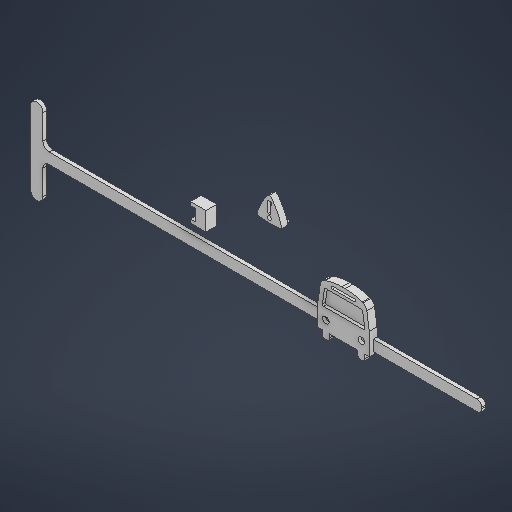
# Autodesk Inventor part: Bus
Saved by Autodesk Inventor 2027 (Build 310192060, 192F)
## iProperties
Created: 2025-09-19
Part Number: Bus
Material: Genérico
Document SubType Name: Modeling
Designer: Pablo
Density: 1 g/cm^3
Appearance: Valor por defecto
Author: Pablo
Autodesk Inventor part; units mm, degrees
(part 1 of 2)
ref_plane "YZ Plane" through (0, 0, 0) normal (1, 0, 0) x (0, 1, 0)
ref_plane "XZ Plane" through (0, 0, 0) normal (0, 1, 0) x (-1, 0, 0)
ref_plane "XY Plane" through (0, 0, 0) normal (0, 0, 1) x (1, 0, 0)
sketch "Boceto1" plane through (0, 0, 0) normal (0, 0, 1) x (1, 0, 0)
  spline S0 degree 3 poles (40.8616, 31.8557) (40.8616, 34.2295) (40.8616, 36.6032) (40.8611, 38.977) knots 0 0 0 0 1 1 1 1
  line L0 (40.8616, 31.8557) -> (40.8616, 34.2295) construction
  line L1 (40.8616, 34.2295) -> (40.8616, 36.6032) construction
  line L2 (40.8616, 36.6032) -> (40.8611, 38.977) construction
  spline S1 degree 3 poles (40.8611, 38.977) (40.8611, 38.9994) (40.8575, 39.0217) (40.856, 39.0441) knots 1 1 1 1 2 2 2 2
  line L3 (40.8611, 38.977) -> (40.8611, 38.9994) construction
  line L4 (40.8611, 38.9994) -> (40.8575, 39.0217) construction
  line L5 (40.8575, 39.0217) -> (40.856, 39.0441) construction
  spline S2 degree 3 poles (40.856, 39.0441) (40.856, 39.3464) (40.856, 39.6488) (40.856, 39.9511) knots 2 2 2 2 3 3 3 3
  line L6 (40.856, 39.0441) -> (40.856, 39.3464) construction
  line L7 (40.856, 39.3464) -> (40.856, 39.6488) construction
  line L8 (40.856, 39.6488) -> (40.856, 39.9511) construction
  spline S3 degree 3 poles (40.856, 39.9511) (40.856, 40.0019) (40.852, 40.053) (40.8445, 40.1033) knots 3 3 3 3 4 4 4 4
  line L9 (40.856, 39.9511) -> (40.856, 40.0019) construction
  line L10 (40.856, 40.0019) -> (40.852, 40.053) construction
  line L11 (40.852, 40.053) -> (40.8445, 40.1033) construction
  spline S4 degree 3 poles (40.8445, 40.1033) (40.7707, 40.601) (40.6955, 41.0985) (40.6214, 41.5961) knots 4 4 4 4 5 5 5 5
  line L12 (40.8445, 40.1033) -> (40.7707, 40.601) construction
  line L13 (40.7707, 40.601) -> (40.6955, 41.0985) construction
  line L14 (40.6955, 41.0985) -> (40.6214, 41.5961) construction
  spline S5 degree 3 poles (40.6214, 41.5961) (40.5322, 42.1946) (40.4442, 42.7933) (40.3549, 43.3918) knots 5 5 5 5 6 6 6 6
  line L15 (40.6214, 41.5961) -> (40.5322, 42.1946) construction
  line L16 (40.5322, 42.1946) -> (40.4442, 42.7933) construction
  line L17 (40.4442, 42.7933) -> (40.3549, 43.3918) construction
  spline S6 degree 3 poles (40.3549, 43.3918) (40.265, 43.9937) (40.1747, 44.5954) (40.0834, 45.1971) knots 6 6 6 6 7 7 7 7
  line L18 (40.3549, 43.3918) -> (40.265, 43.9937) construction
  line L19 (40.265, 43.9937) -> (40.1747, 44.5954) construction
  line L20 (40.1747, 44.5954) -> (40.0834, 45.1971) construction
  spline S7 degree 3 poles (40.0834, 45.1971) (40.0103, 45.68) (39.7786, 46.0909) (39.3479, 46.409) knots 7 7 7 7 8 8 8 8
  line L21 (40.0834, 45.1971) -> (40.0103, 45.68) construction
  line L22 (40.0103, 45.68) -> (39.7786, 46.0909) construction
  line L23 (39.7786, 46.0909) -> (39.3479, 46.409) construction
  spline S8 degree 3 poles (39.3479, 46.409) (38.9282, 46.7189) (38.4358, 46.9172) (37.9249, 47.0751) knots 8 8 8 8 9 9 9 9
  line L24 (39.3479, 46.409) -> (38.9282, 46.7189) construction
  line L25 (38.9282, 46.7189) -> (38.4358, 46.9172) construction
  line L26 (38.4358, 46.9172) -> (37.9249, 47.0751) construction
  spline S9 degree 3 poles (37.9249, 47.0751) (36.5997, 47.4845) (35.2232, 47.6868) (33.8295, 47.8099) knots 9 9 9 9 10 10 10 10
  line L27 (37.9249, 47.0751) -> (36.5997, 47.4845) construction
  line L28 (36.5997, 47.4845) -> (35.2232, 47.6868) construction
  line L29 (35.2232, 47.6868) -> (33.8295, 47.8099) construction
  spline S10 degree 3 poles (33.8295, 47.8099) (33.0432, 47.8793) (32.2577, 47.8666) (31.4714, 47.7946) knots 10 10 10 10 11 11 11 11
  line L30 (33.8295, 47.8099) -> (33.0432, 47.8793) construction
  line L31 (33.0432, 47.8793) -> (32.2577, 47.8666) construction
  line L32 (32.2577, 47.8666) -> (31.4714, 47.7946) construction
  spline S11 degree 3 poles (31.4714, 47.7946) (30.5096, 47.7066) (29.5599, 47.5625) (28.6214, 47.3611) knots 11 11 11 11 12 12 12 12
  line L33 (31.4714, 47.7946) -> (30.5096, 47.7066) construction
  line L34 (30.5096, 47.7066) -> (29.5599, 47.5625) construction
  line L35 (29.5599, 47.5625) -> (28.6214, 47.3611) construction
  spline S12 degree 3 poles (28.6214, 47.3611) (27.8894, 47.204) (27.1802, 46.9945) (26.5251, 46.6616) knots 12 12 12 12 13 13 13 13
  line L36 (28.6214, 47.3611) -> (27.8894, 47.204) construction
  line L37 (27.8894, 47.204) -> (27.1802, 46.9945) construction
  line L38 (27.1802, 46.9945) -> (26.5251, 46.6616) construction
  spline S13 degree 3 poles (26.5251, 46.6616) (25.8871, 46.3373) (25.4918, 45.8668) (25.386, 45.2249) knots 13 13 13 13 14 14 14 14
  line L39 (26.5251, 46.6616) -> (25.8871, 46.3373) construction
  line L40 (25.8871, 46.3373) -> (25.4918, 45.8668) construction
  line L41 (25.4918, 45.8668) -> (25.386, 45.2249) construction
  spline S14 degree 3 poles (25.386, 45.2249) (25.3274, 44.8691) (25.2811, 44.5119) (25.2281, 44.1554) knots 14 14 14 14 15 15 15 15
  line L42 (25.386, 45.2249) -> (25.3274, 44.8691) construction
  line L43 (25.3274, 44.8691) -> (25.2811, 44.5119) construction
  line L44 (25.2811, 44.5119) -> (25.2281, 44.1554) construction
  spline S15 degree 3 poles (25.2281, 44.1554) (25.146, 43.6039) (25.0628, 43.0526) (24.9803, 42.5012) knots 15 15 15 15 16 16 16 16
  line L45 (25.2281, 44.1554) -> (25.146, 43.6039) construction
  line L46 (25.146, 43.6039) -> (25.0628, 43.0526) construction
  line L47 (25.0628, 43.0526) -> (24.9803, 42.5012) construction
  spline S16 degree 3 poles (24.9803, 42.5012) (24.8978, 41.9498) (24.8143, 41.3985) (24.7336, 40.8469) knots 16 16 16 16 17 17 17 17
  line L48 (24.9803, 42.5012) -> (24.8978, 41.9498) construction
  line L49 (24.8978, 41.9498) -> (24.8143, 41.3985) construction
  line L50 (24.8143, 41.3985) -> (24.7336, 40.8469) construction
  spline S17 degree 3 poles (24.7336, 40.8469) (24.6889, 40.541) (24.614, 40.2346) (24.6127, 39.9282) knots 17 17 17 17 18 18 18 18
  line L51 (24.7336, 40.8469) -> (24.6889, 40.541) construction
  line L52 (24.6889, 40.541) -> (24.614, 40.2346) construction
  line L53 (24.614, 40.2346) -> (24.6127, 39.9282) construction
  spline S18 degree 3 poles (24.6127, 39.9282) (24.6051, 38.1413) (24.6059, 36.3544) (24.6067, 34.5675) knots 18 18 18 18 19 19 19 19
  line L54 (24.6127, 39.9282) -> (24.6051, 38.1413) construction
  line L55 (24.6051, 38.1413) -> (24.6059, 36.3544) construction
  line L56 (24.6059, 36.3544) -> (24.6067, 34.5675) construction
  spline S19 degree 3 poles (24.6067, 34.5675) (24.6065, 34.0719) (24.6063, 33.5763) (24.6065, 33.0807) knots 19 19 19 19 20 20 20 20
  line L57 (24.6067, 34.5675) -> (24.6065, 34.0719) construction
  line L58 (24.6065, 34.0719) -> (24.6063, 33.5763) construction
  line L59 (24.6063, 33.5763) -> (24.6065, 33.0807) construction
  spline S20 degree 3 poles (24.6065, 33.0807) (24.6062, 31.8371) (24.6072, 30.5935) (24.6072, 29.3499) (24.6072, 29.3132) (24.6072, 29.2766) (24.6072, 29.2237) knots 20 20 20 20 21 21 21 22 22 22 22
  line L60 (24.6065, 33.0807) -> (24.6062, 31.8371) construction
  line L61 (24.6062, 31.8371) -> (24.6072, 30.5935) construction
  line L62 (24.6072, 30.5935) -> (24.6072, 29.3499) construction
  line L63 (24.6072, 29.3499) -> (24.6072, 29.3132) construction
  line L64 (24.6072, 29.3132) -> (24.6072, 29.2766) construction
  line L65 (24.6072, 29.2766) -> (24.6072, 29.2237) construction
  spline S21 degree 3 poles (24.6072, 29.2237) (25.0641, 29.2237) (25.5097, 29.2237) (25.9657, 29.2237) knots 22 22 22 22 23 23 23 23
  line L66 (24.6072, 29.2237) -> (25.0641, 29.2237) construction
  line L67 (25.0641, 29.2237) -> (25.5097, 29.2237) construction
  line L68 (25.5097, 29.2237) -> (25.9657, 29.2237) construction
  spline S22 degree 3 poles (25.9657, 29.2237) (25.9657, 29.1676) (25.9657, 29.1275) (25.9658, 29.0874) knots 23 23 23 23 24 24 24 24
  line L69 (25.9657, 29.2237) -> (25.9657, 29.1676) construction
  line L70 (25.9657, 29.1676) -> (25.9657, 29.1275) construction
  line L71 (25.9657, 29.1275) -> (25.9658, 29.0874) construction
  spline S23 degree 3 poles (25.9658, 29.0874) (25.9661, 28.7444) (25.9588, 28.4012) (25.9685, 28.0584) knots 24 24 24 24 25 25 25 25
  line L72 (25.9658, 29.0874) -> (25.9661, 28.7444) construction
  line L73 (25.9661, 28.7444) -> (25.9588, 28.4012) construction
  line L74 (25.9588, 28.4012) -> (25.9685, 28.0584) construction
  spline S24 degree 3 poles (25.9685, 28.0584) (25.9929, 27.1984) (26.891, 26.8938) (27.5599, 27.098) knots 25 25 25 25 26 26 26 26
  line L75 (25.9685, 28.0584) -> (25.9929, 27.1984) construction
  line L76 (25.9929, 27.1984) -> (26.891, 26.8938) construction
  line L77 (26.891, 26.8938) -> (27.5599, 27.098) construction
  spline S25 degree 3 poles (27.5599, 27.098) (27.9931, 27.2303) (28.295, 27.5697) (28.3094, 27.9733) knots 26 26 26 26 27 27 27 27
  line L78 (27.5599, 27.098) -> (27.9931, 27.2303) construction
  line L79 (27.9931, 27.2303) -> (28.295, 27.5697) construction
  line L80 (28.295, 27.5697) -> (28.3094, 27.9733) construction
  spline S26 degree 3 poles (28.3094, 27.9733) (28.3227, 28.3465) (28.3153, 28.7203) (28.3169, 29.0939) knots 27 27 27 27 28 28 28 28
  line L81 (28.3094, 27.9733) -> (28.3227, 28.3465) construction
  line L82 (28.3227, 28.3465) -> (28.3153, 28.7203) construction
  line L83 (28.3153, 28.7203) -> (28.3169, 29.0939) construction
  spline S27 degree 3 poles (28.3169, 29.0939) (28.3171, 29.1335) (28.317, 29.1732) (28.317, 29.2165) knots 28 28 28 28 29 29 29 29
  line L84 (28.3169, 29.0939) -> (28.3171, 29.1335) construction
  line L85 (28.3171, 29.1335) -> (28.317, 29.1732) construction
  line L86 (28.317, 29.1732) -> (28.317, 29.2165) construction
  spline S28 degree 3 poles (28.317, 29.2165) (31.2685, 29.2165) (34.2031, 29.2165) (37.1493, 29.2165) knots 29 29 29 29 30 30 30 30
  line L87 (28.317, 29.2165) -> (31.2685, 29.2165) construction
  line L88 (31.2685, 29.2165) -> (34.2031, 29.2165) construction
  line L89 (34.2031, 29.2165) -> (37.1493, 29.2165) construction
  spline S29 degree 3 poles (37.1493, 29.2165) (37.1493, 29.1729) (37.1493, 29.1363) (37.1493, 29.0996) knots 30 30 30 30 31 31 31 31
  line L90 (37.1493, 29.2165) -> (37.1493, 29.1729) construction
  line L91 (37.1493, 29.1729) -> (37.1493, 29.1363) construction
  line L92 (37.1493, 29.1363) -> (37.1493, 29.0996) construction
  spline S30 degree 3 poles (37.1493, 29.0996) (37.1495, 28.7465) (37.1476, 28.3933) (37.1509, 28.0401) knots 31 31 31 31 32 32 32 32
  line L93 (37.1493, 29.0996) -> (37.1495, 28.7465) construction
  line L94 (37.1495, 28.7465) -> (37.1476, 28.3933) construction
  line L95 (37.1476, 28.3933) -> (37.1509, 28.0401) construction
  spline S31 degree 3 poles (37.1509, 28.0401) (37.1525, 27.854) (37.2057, 27.6778) (37.3152, 27.5165) knots 32 32 32 32 33 33 33 33
  line L96 (37.1509, 28.0401) -> (37.1525, 27.854) construction
  line L97 (37.1525, 27.854) -> (37.2057, 27.6778) construction
  line L98 (37.2057, 27.6778) -> (37.3152, 27.5165) construction
  spline S32 degree 3 poles (37.3152, 27.5165) (37.5769, 27.131) (38.1197, 26.9538) (38.6595, 27.0769) knots 33 33 33 33 34 34 34 34
  line L99 (37.3152, 27.5165) -> (37.5769, 27.131) construction
  line L100 (37.5769, 27.131) -> (38.1197, 26.9538) construction
  line L101 (38.1197, 26.9538) -> (38.6595, 27.0769) construction
  spline S33 degree 3 poles (38.6595, 27.0769) (39.1527, 27.1894) (39.4892, 27.5688) (39.4966, 28.032) knots 34 34 34 34 35 35 35 35
  line L102 (38.6595, 27.0769) -> (39.1527, 27.1894) construction
  line L103 (39.1527, 27.1894) -> (39.4892, 27.5688) construction
  line L104 (39.4892, 27.5688) -> (39.4966, 28.032) construction
  spline S34 degree 3 poles (39.4966, 28.032) (39.5025, 28.3885) (39.498, 28.7451) (39.4982, 29.1017) knots 35 35 35 35 36 36 36 36
  line L105 (39.4966, 28.032) -> (39.5025, 28.3885) construction
  line L106 (39.5025, 28.3885) -> (39.498, 28.7451) construction
  line L107 (39.498, 28.7451) -> (39.4982, 29.1017) construction
  spline S35 degree 3 poles (39.4982, 29.1017) (39.4982, 29.1381) (39.4982, 29.1745) (39.4982, 29.2229) knots 36 36 36 36 37 37 37 37
  line L108 (39.4982, 29.1017) -> (39.4982, 29.1381) construction
  line L109 (39.4982, 29.1381) -> (39.4982, 29.1745) construction
  line L110 (39.4982, 29.1745) -> (39.4982, 29.2229) construction
  spline S36 degree 3 poles (39.4982, 29.2229) (39.9535, 29.2229) (40.3962, 29.2229) (40.8565, 29.2229) knots 37 37 37 37 38 38 38 38
  line L111 (39.4982, 29.2229) -> (39.9535, 29.2229) construction
  line L112 (39.9535, 29.2229) -> (40.3962, 29.2229) construction
  line L113 (40.3962, 29.2229) -> (40.8565, 29.2229) construction
  spline S37 degree 3 poles (40.8565, 29.2229) (40.8565, 29.275) (40.8565, 29.3086) (40.8565, 29.3422) (40.8565, 29.767) (40.8564, 30.1918) (40.8564, 30.6166) knots 38 38 38 38 39 39 39 40 40 40 40
  line L114 (40.8565, 29.2229) -> (40.8565, 29.275) construction
  line L115 (40.8565, 29.275) -> (40.8565, 29.3086) construction
  line L116 (40.8565, 29.3086) -> (40.8565, 29.3422) construction
  line L117 (40.8565, 29.3422) -> (40.8565, 29.767) construction
  line L118 (40.8565, 29.767) -> (40.8564, 30.1918) construction
  line L119 (40.8564, 30.1918) -> (40.8564, 30.6166) construction
  line L120 (40.8564, 30.6166) -> (40.8565, 30.6166)
  spline S38 degree 3 poles (40.8565, 30.6166) (40.8565, 30.6686) (40.8565, 30.7022) (40.8565, 30.7359) (40.8565, 31.0694) (40.8564, 31.4029) (40.8564, 31.7364) knots 41 41 41 41 42 42 42 43 43 43 43
  line L121 (40.8565, 30.6166) -> (40.8565, 30.6686) construction
  line L122 (40.8565, 30.6686) -> (40.8565, 30.7022) construction
  line L123 (40.8565, 30.7022) -> (40.8565, 30.7359) construction
  line L124 (40.8565, 30.7359) -> (40.8565, 31.0694) construction
  line L125 (40.8565, 31.0694) -> (40.8564, 31.4029) construction
  line L126 (40.8564, 31.4029) -> (40.8564, 31.7364) construction
  spline S39 degree 3 poles (40.8564, 31.7364) (40.8581, 31.7364) (40.8598, 31.7364) (40.8616, 31.7364) knots 43 43 43 43 44 44 44 44
  line L127 (40.8564, 31.7364) -> (40.8581, 31.7364) construction
  line L128 (40.8581, 31.7364) -> (40.8598, 31.7364) construction
  line L129 (40.8598, 31.7364) -> (40.8616, 31.7364) construction
  spline S40 degree 3 poles (40.8616, 31.7364) (40.8616, 31.7885) (40.8616, 31.8221) (40.8616, 31.8557) knots 44 44 44 44 45 45 45 45
  line L130 (40.8616, 31.7364) -> (40.8616, 31.7885) construction
  line L131 (40.8616, 31.7885) -> (40.8616, 31.8221) construction
  line L132 (40.8616, 31.8221) -> (40.8616, 31.8557) construction
  spline S41 degree 3 poles (34.2345, 42.6962) (35.0073, 42.6962) (35.7802, 42.6959) (36.553, 42.6956) (36.5571, 42.6769) (36.5618, 42.6586) (36.5635, 42.6386) (36.586, 42.3716) (36.3803, 42.1817) (36.0592, 42.1812) (34.9481, 42.1798) (33.837, 42.1807) (32.7258, 42.1807) (31.6225, 42.1806) (30.5192, 42.18) (29.4159, 42.181) (29.128, 42.1813) (28.9588, 42.3013) (28.9123, 42.5307) (28.9007, 42.5881) (28.903, 42.6429) (28.9139, 42.6946) (30.6875, 42.6957) (32.461, 42.696) (34.2345, 42.6962) knots 0 0 0 0 1 1 1 2 2 2 3 3 3 4 4 4 5 5 5 6 6 6 7 7 7 8 8 8 8
  line L133 (34.2345, 42.6962) -> (35.0073, 42.6962) construction
  line L134 (35.0073, 42.6962) -> (35.7802, 42.6959) construction
  line L135 (35.7802, 42.6959) -> (36.553, 42.6956) construction
  line L136 (36.553, 42.6956) -> (36.5571, 42.6769) construction
  line L137 (36.5571, 42.6769) -> (36.5618, 42.6586) construction
  line L138 (36.5618, 42.6586) -> (36.5635, 42.6386) construction
  line L139 (36.5635, 42.6386) -> (36.586, 42.3716) construction
  line L140 (36.586, 42.3716) -> (36.3803, 42.1817) construction
  line L141 (36.3803, 42.1817) -> (36.0592, 42.1812) construction
  line L142 (36.0592, 42.1812) -> (34.9481, 42.1798) construction
  line L143 (34.9481, 42.1798) -> (33.837, 42.1807) construction
  line L144 (33.837, 42.1807) -> (32.7258, 42.1807) construction
  line L145 (32.7258, 42.1807) -> (31.6225, 42.1806) construction
  line L146 (31.6225, 42.1806) -> (30.5192, 42.18) construction
  line L147 (30.5192, 42.18) -> (29.4159, 42.181) construction
  line L148 (29.4159, 42.181) -> (29.128, 42.1813) construction
  line L149 (29.128, 42.1813) -> (28.9588, 42.3013) construction
  line L150 (28.9588, 42.3013) -> (28.9123, 42.5307) construction
  line L151 (28.9123, 42.5307) -> (28.9007, 42.5881) construction
  line L152 (28.9007, 42.5881) -> (28.903, 42.6429) construction
  line L153 (28.903, 42.6429) -> (28.9139, 42.6946) construction
  line L154 (28.9139, 42.6946) -> (30.6875, 42.6957) construction
  line L155 (30.6875, 42.6957) -> (32.461, 42.696) construction
  line L156 (32.461, 42.696) -> (34.2345, 42.6962) construction
  spline S42 degree 3 poles (26.564, 39.4612) (26.5391, 39.4643) (26.5166, 39.4697) (26.4932, 39.4744) (26.556, 39.8745) (26.6178, 40.2748) (26.6981, 40.6722) (26.7877, 41.1148) (27.0588, 41.2999) (27.5762, 41.3006) (29.7957, 41.3033) (32.0151, 41.3022) (34.2345, 41.3025) (35.4124, 41.3026) (36.5905, 41.303) (37.7684, 41.3016) (37.8849, 41.3015) (38.0023, 41.2957) (38.1176, 41.2817) (38.4206, 41.2449) (38.632, 41.0974) (38.7143, 40.8428) (38.7815, 40.6351) (38.8204, 40.4195) (38.8562, 40.2054) (38.8971, 39.9608) (38.9349, 39.7159) (38.9744, 39.4711) (38.9349, 39.4639) (38.894, 39.4585) (38.8504, 39.4567) (38.7921, 39.4542) (38.7334, 39.4555) (38.6749, 39.4555) (36.6935, 39.4554) (34.712, 39.4554) (32.7304, 39.4554) (30.745, 39.4554) (28.7597, 39.4554) (26.7743, 39.4556) (26.7041, 39.4556) (26.633, 39.4526) (26.564, 39.4612) knots 0 0 0 0 1 1 1 2 2 2 3 3 3 4 4 4 5 5 5 6 6 6 7 7 7 8 8 8 9 9 9 10 10 10 11 11 11 12 12 12 13 13 13 14 14 14 14
  line L157 (26.564, 39.4612) -> (26.5391, 39.4643) construction
  line L158 (26.5391, 39.4643) -> (26.5166, 39.4697) construction
  line L159 (26.5166, 39.4697) -> (26.4932, 39.4744) construction
  line L160 (26.4932, 39.4744) -> (26.556, 39.8745) construction
  line L161 (26.556, 39.8745) -> (26.6178, 40.2748) construction
  line L162 (26.6178, 40.2748) -> (26.6981, 40.6722) construction
  line L163 (26.6981, 40.6722) -> (26.7877, 41.1148) construction
  line L164 (26.7877, 41.1148) -> (27.0588, 41.2999) construction
  line L165 (27.0588, 41.2999) -> (27.5762, 41.3006) construction
  line L166 (27.5762, 41.3006) -> (29.7957, 41.3033) construction
  line L167 (29.7957, 41.3033) -> (32.0151, 41.3022) construction
  line L168 (32.0151, 41.3022) -> (34.2345, 41.3025) construction
  line L169 (34.2345, 41.3025) -> (35.4124, 41.3026) construction
  line L170 (35.4124, 41.3026) -> (36.5905, 41.303) construction
  line L171 (36.5905, 41.303) -> (37.7684, 41.3016) construction
  line L172 (37.7684, 41.3016) -> (37.8849, 41.3015) construction
  line L173 (37.8849, 41.3015) -> (38.0023, 41.2957) construction
  line L174 (38.0023, 41.2957) -> (38.1176, 41.2817) construction
  line L175 (38.1176, 41.2817) -> (38.4206, 41.2449) construction
  line L176 (38.4206, 41.2449) -> (38.632, 41.0974) construction
  line L177 (38.632, 41.0974) -> (38.7143, 40.8428) construction
  line L178 (38.7143, 40.8428) -> (38.7815, 40.6351) construction
  line L179 (38.7815, 40.6351) -> (38.8204, 40.4195) construction
  line L180 (38.8204, 40.4195) -> (38.8562, 40.2054) construction
  line L181 (38.8562, 40.2054) -> (38.8971, 39.9608) construction
  line L182 (38.8971, 39.9608) -> (38.9349, 39.7159) construction
  line L183 (38.9349, 39.7159) -> (38.9744, 39.4711) construction
  line L184 (38.9744, 39.4711) -> (38.9349, 39.4639) construction
  line L185 (38.9349, 39.4639) -> (38.894, 39.4585) construction
  line L186 (38.894, 39.4585) -> (38.8504, 39.4567) construction
  line L187 (38.8504, 39.4567) -> (38.7921, 39.4542) construction
  line L188 (38.7921, 39.4542) -> (38.7334, 39.4555) construction
  line L189 (38.7334, 39.4555) -> (38.6749, 39.4555) construction
  line L190 (38.6749, 39.4555) -> (36.6935, 39.4554) construction
  line L191 (36.6935, 39.4554) -> (34.712, 39.4554) construction
  line L192 (34.712, 39.4554) -> (32.7304, 39.4554) construction
  line L193 (32.7304, 39.4554) -> (30.745, 39.4554) construction
  line L194 (30.745, 39.4554) -> (28.7597, 39.4554) construction
  line L195 (28.7597, 39.4554) -> (26.7743, 39.4556) construction
  line L196 (26.7743, 39.4556) -> (26.7041, 39.4556) construction
  line L197 (26.7041, 39.4556) -> (26.633, 39.4526) construction
  line L198 (26.633, 39.4526) -> (26.564, 39.4612) construction
  spline S43 degree 3 poles (40.4002, 7.2187) (39.938, 7.2187) (39.4935, 7.2187) (39.0362, 7.2187) (39.0362, 7.1702) (39.0362, 7.1337) (39.0362, 7.0972) (39.0361, 6.7401) (39.0405, 6.3829) (39.0347, 6.0258) (39.0272, 5.5619) (38.6893, 5.1819) (38.194, 5.0692) (37.6521, 4.9459) (37.107, 5.1234) (36.8441, 5.5095) (36.7342, 5.6711) (36.6808, 5.8475) (36.6791, 6.034) (36.6759, 6.3877) (36.6778, 6.7414) (36.6775, 7.0952) (36.6775, 7.1319) (36.6775, 7.1686) (36.6775, 7.2122) (33.719, 7.2122) (30.7722, 7.2122) (27.8084, 7.2122) (27.8084, 7.1688) (27.8085, 7.1291) (27.8084, 7.0894) (27.8067, 6.7153) (27.8142, 6.3409) (27.8008, 5.9671) (27.7863, 5.5628) (27.4832, 5.2229) (27.0481, 5.0904) (26.3765, 4.8859) (25.4746, 5.1909) (25.4501, 6.0523) (25.4404, 6.3956) (25.4478, 6.7393) (25.4474, 7.0829) (25.4473, 7.1231) (25.4474, 7.1633) (25.4474, 7.2195) (24.9895, 7.2195) (24.542, 7.2195) (24.0831, 7.2195) (24.0831, 7.2724) (24.0831, 7.3091) (24.0831, 7.3458) (24.0831, 9.7132) (24.0786, 12.0805) (24.0887, 14.4478) (24.0901, 14.7547) (24.1652, 15.0615) (24.2101, 15.368) (24.2911, 15.9205) (24.375, 16.4726) (24.4579, 17.0249) (24.5407, 17.5772) (24.6242, 18.1294) (24.7066, 18.6817) (24.7599, 19.0387) (24.8064, 19.3966) (24.8652, 19.7529) (24.9714, 20.3959) (25.3684, 20.8671) (26.009, 21.1919) (26.6669, 21.5253) (27.3791, 21.7351) (28.1141, 21.8925) (29.0565, 22.0942) (30.0102, 22.2385) (30.976, 22.3267) (31.7656, 22.3988) (32.5544, 22.4116) (33.3439, 22.342) (34.7435, 22.2188) (36.1257, 22.0161) (37.4564, 21.606) (37.9694, 21.4479) (38.4638, 21.2493) (38.8853, 20.9389) (39.3179, 20.6203) (39.5504, 20.2087) (39.624, 19.7251) (39.7156, 19.1225) (39.8063, 18.5197) (39.8965, 17.9169) (39.9863, 17.3174) (40.0746, 16.7178) (40.1641, 16.1183) (40.2385, 15.6199) (40.3141, 15.1216) (40.3882, 14.6231) (40.3956, 14.5727) (40.3997, 14.5216) (40.3997, 14.4708) (40.4002, 12.0932) (40.4002, 9.7157) (40.4002, 7.3381) (40.4002, 7.3044) (40.4002, 7.2708) (40.4002, 7.2187) knots 0 0 0 0 1 1 1 2 2 2 3 3 3 4 4 4 5 5 5 6 6 6 7 7 7 8 8 8 9 9 9 10 10 10 11 11 11 12 12 12 13 13 13 14 14 14 15 15 15 16 16 16 17 17 17 18 18 18 19 19 19 20 20 20 21 21 21 22 22 22 23 23 23 24 24 24 25 25 25 26 26 26 27 27 27 28 28 28 29 29 29 30 30 30 31 31 31 32 32 32 33 33 33 34 34 34 35 35 35 35
  line L199 (40.4002, 7.2187) -> (39.938, 7.2187) construction
  line L200 (39.938, 7.2187) -> (39.4935, 7.2187) construction
  line L201 (39.4935, 7.2187) -> (39.0362, 7.2187) construction
  line L202 (39.0362, 7.2187) -> (39.0362, 7.1702) construction
  line L203 (39.0362, 7.1702) -> (39.0362, 7.1337) construction
  line L204 (39.0362, 7.1337) -> (39.0362, 7.0972) construction
  line L205 (39.0362, 7.0972) -> (39.0361, 6.7401) construction
  line L206 (39.0361, 6.7401) -> (39.0405, 6.3829) construction
  line L207 (39.0405, 6.3829) -> (39.0347, 6.0258) construction
  line L208 (39.0347, 6.0258) -> (39.0272, 5.5619) construction
  line L209 (39.0272, 5.5619) -> (38.6893, 5.1819) construction
  line L210 (38.6893, 5.1819) -> (38.194, 5.0692) construction
  line L211 (38.194, 5.0692) -> (37.6521, 4.9459) construction
  line L212 (37.6521, 4.9459) -> (37.107, 5.1234) construction
  line L213 (37.107, 5.1234) -> (36.8441, 5.5095) construction
  line L214 (36.8441, 5.5095) -> (36.7342, 5.6711) construction
  line L215 (36.7342, 5.6711) -> (36.6808, 5.8475) construction
  line L216 (36.6808, 5.8475) -> (36.6791, 6.034) construction
  line L217 (36.6791, 6.034) -> (36.6759, 6.3877) construction
  line L218 (36.6759, 6.3877) -> (36.6778, 6.7414) construction
  line L219 (36.6778, 6.7414) -> (36.6775, 7.0952) construction
  line L220 (36.6775, 7.0952) -> (36.6775, 7.1319) construction
  line L221 (36.6775, 7.1319) -> (36.6775, 7.1686) construction
  line L222 (36.6775, 7.1686) -> (36.6775, 7.2122) construction
  line L223 (36.6775, 7.2122) -> (33.719, 7.2122) construction
  line L224 (33.719, 7.2122) -> (30.7722, 7.2122) construction
  line L225 (30.7722, 7.2122) -> (27.8084, 7.2122) construction
  line L226 (27.8084, 7.2122) -> (27.8084, 7.1688) construction
  line L227 (27.8084, 7.1688) -> (27.8085, 7.1291) construction
  line L228 (27.8085, 7.1291) -> (27.8084, 7.0894) construction
  line L229 (27.8084, 7.0894) -> (27.8067, 6.7153) construction
  line L230 (27.8067, 6.7153) -> (27.8142, 6.3409) construction
  line L231 (27.8142, 6.3409) -> (27.8008, 5.9671) construction
  line L232 (27.8008, 5.9671) -> (27.7863, 5.5628) construction
  line L233 (27.7863, 5.5628) -> (27.4832, 5.2229) construction
  line L234 (27.4832, 5.2229) -> (27.0481, 5.0904) construction
  line L235 (27.0481, 5.0904) -> (26.3765, 4.8859) construction
  line L236 (26.3765, 4.8859) -> (25.4746, 5.1909) construction
  line L237 (25.4746, 5.1909) -> (25.4501, 6.0523) construction
  line L238 (25.4501, 6.0523) -> (25.4404, 6.3956) construction
  line L239 (25.4404, 6.3956) -> (25.4478, 6.7393) construction
  line L240 (25.4478, 6.7393) -> (25.4474, 7.0829) construction
  line L241 (25.4474, 7.0829) -> (25.4473, 7.1231) construction
  line L242 (25.4473, 7.1231) -> (25.4474, 7.1633) construction
  line L243 (25.4474, 7.1633) -> (25.4474, 7.2195) construction
  line L244 (25.4474, 7.2195) -> (24.9895, 7.2195) construction
  line L245 (24.9895, 7.2195) -> (24.542, 7.2195) construction
  line L246 (24.542, 7.2195) -> (24.0831, 7.2195) construction
  line L247 (24.0831, 7.2195) -> (24.0831, 7.2724) construction
  line L248 (24.0831, 7.2724) -> (24.0831, 7.3091) construction
  line L249 (24.0831, 7.3091) -> (24.0831, 7.3458) construction
  line L250 (24.0831, 7.3458) -> (24.0831, 9.7132) construction
  line L251 (24.0831, 9.7132) -> (24.0786, 12.0805) construction
  line L252 (24.0786, 12.0805) -> (24.0887, 14.4478) construction
  line L253 (24.0887, 14.4478) -> (24.0901, 14.7547) construction
  line L254 (24.0901, 14.7547) -> (24.1652, 15.0615) construction
  line L255 (24.1652, 15.0615) -> (24.2101, 15.368) construction
  line L256 (24.2101, 15.368) -> (24.2911, 15.9205) construction
  line L257 (24.2911, 15.9205) -> (24.375, 16.4726) construction
  line L258 (24.375, 16.4726) -> (24.4579, 17.0249) construction
  line L259 (24.4579, 17.0249) -> (24.5407, 17.5772) construction
  line L260 (24.5407, 17.5772) -> (24.6242, 18.1294) construction
  line L261 (24.6242, 18.1294) -> (24.7066, 18.6817) construction
  line L262 (24.7066, 18.6817) -> (24.7599, 19.0387) construction
  line L263 (24.7599, 19.0387) -> (24.8064, 19.3966) construction
  line L264 (24.8064, 19.3966) -> (24.8652, 19.7529) construction
  line L265 (24.8652, 19.7529) -> (24.9714, 20.3959) construction
  line L266 (24.9714, 20.3959) -> (25.3684, 20.8671) construction
  line L267 (25.3684, 20.8671) -> (26.009, 21.1919) construction
  line L268 (26.009, 21.1919) -> (26.6669, 21.5253) construction
  line L269 (26.6669, 21.5253) -> (27.3791, 21.7351) construction
  line L270 (27.3791, 21.7351) -> (28.1141, 21.8925) construction
  line L271 (28.1141, 21.8925) -> (29.0565, 22.0942) construction
  line L272 (29.0565, 22.0942) -> (30.0102, 22.2385) construction
  line L273 (30.0102, 22.2385) -> (30.976, 22.3267) construction
  line L274 (30.976, 22.3267) -> (31.7656, 22.3988) construction
  line L275 (31.7656, 22.3988) -> (32.5544, 22.4116) construction
  line L276 (32.5544, 22.4116) -> (33.3439, 22.342) construction
  line L277 (33.3439, 22.342) -> (34.7435, 22.2188) construction
  line L278 (34.7435, 22.2188) -> (36.1257, 22.0161) construction
  line L279 (36.1257, 22.0161) -> (37.4564, 21.606) construction
  line L280 (37.4564, 21.606) -> (37.9694, 21.4479) construction
  line L281 (37.9694, 21.4479) -> (38.4638, 21.2493) construction
  line L282 (38.4638, 21.2493) -> (38.8853, 20.9389) construction
  line L283 (38.8853, 20.9389) -> (39.3179, 20.6203) construction
  line L284 (39.3179, 20.6203) -> (39.5504, 20.2087) construction
  line L285 (39.5504, 20.2087) -> (39.624, 19.7251) construction
  line L286 (39.624, 19.7251) -> (39.7156, 19.1225) construction
  line L287 (39.7156, 19.1225) -> (39.8063, 18.5197) construction
  line L288 (39.8063, 18.5197) -> (39.8965, 17.9169) construction
  line L289 (39.8965, 17.9169) -> (39.9863, 17.3174) construction
  line L290 (39.9863, 17.3174) -> (40.0746, 16.7178) construction
  line L291 (40.0746, 16.7178) -> (40.1641, 16.1183) construction
  line L292 (40.1641, 16.1183) -> (40.2385, 15.6199) construction
  line L293 (40.2385, 15.6199) -> (40.3141, 15.1216) construction
  line L294 (40.3141, 15.1216) -> (40.3882, 14.6231) construction
  line L295 (40.3882, 14.6231) -> (40.3956, 14.5727) construction
  line L296 (40.3956, 14.5727) -> (40.3997, 14.5216) construction
  line L297 (40.3997, 14.5216) -> (40.3997, 14.4708) construction
  line L298 (40.3997, 14.4708) -> (40.4002, 12.0932) construction
  line L299 (40.4002, 12.0932) -> (40.4002, 9.7157) construction
  line L300 (40.4002, 9.7157) -> (40.4002, 7.3381) construction
  line L301 (40.4002, 7.3381) -> (40.4002, 7.3044) construction
  line L302 (40.4002, 7.3044) -> (40.4002, 7.2708) construction
  line L303 (40.4002, 7.2708) -> (40.4002, 7.2187) construction
  spline S44 degree 3 poles (32.2403, 13.9743) (34.23, 13.9743) (36.2198, 13.9743) (38.2096, 13.9743) (38.2683, 13.9743) (38.3272, 13.9731) (38.3858, 13.9755) (38.6901, 13.9883) (38.8981, 14.1346) (38.9505, 14.3819) (38.9672, 14.4612) (38.9724, 14.5458) (38.9606, 14.6256) (38.8819, 15.1577) (38.7984, 15.6894) (38.714, 16.2209) (38.6083, 16.887) (38.5032, 17.5532) (38.3916, 18.2186) (38.3556, 18.433) (38.3166, 18.649) (38.2491, 18.857) (38.1664, 19.1121) (37.9542, 19.2598) (37.6499, 19.2966) (37.5341, 19.3106) (37.4162, 19.3165) (37.2993, 19.3166) (36.1164, 19.318) (34.9335, 19.3176) (33.7506, 19.3174) (31.5219, 19.3172) (29.2933, 19.3182) (27.0646, 19.3155) (26.545, 19.3149) (26.2727, 19.1294) (26.1828, 18.6861) (26.0791, 18.1748) (26.0064, 17.6586) (25.9225, 17.1442) (25.8227, 16.5323) (25.723, 15.9203) (25.628, 15.3077) (25.5863, 15.0388) (25.5377, 14.769) (25.5261, 14.4986) (25.5135, 14.2034) (25.7129, 14.0216) (26.0482, 13.98) (26.1174, 13.9715) (26.1889, 13.9745) (26.2593, 13.9745) (28.2529, 13.9742) (30.2466, 13.9743) (32.2403, 13.9743) knots 0 0 0 0 1 1 1 2 2 2 3 3 3 4 4 4 5 5 5 6 6 6 7 7 7 8 8 8 9 9 9 10 10 10 11 11 11 12 12 12 13 13 13 14 14 14 15 15 15 16 16 16 17 17 17 18 18 18 18
  line L304 (32.2403, 13.9743) -> (34.23, 13.9743) construction
  line L305 (34.23, 13.9743) -> (36.2198, 13.9743) construction
  line L306 (36.2198, 13.9743) -> (38.2096, 13.9743) construction
  line L307 (38.2096, 13.9743) -> (38.2683, 13.9743) construction
  line L308 (38.2683, 13.9743) -> (38.3272, 13.9731) construction
  line L309 (38.3272, 13.9731) -> (38.3858, 13.9755) construction
  line L310 (38.3858, 13.9755) -> (38.6901, 13.9883) construction
  line L311 (38.6901, 13.9883) -> (38.8981, 14.1346) construction
  line L312 (38.8981, 14.1346) -> (38.9505, 14.3819) construction
  line L313 (38.9505, 14.3819) -> (38.9672, 14.4612) construction
  line L314 (38.9672, 14.4612) -> (38.9724, 14.5458) construction
  line L315 (38.9724, 14.5458) -> (38.9606, 14.6256) construction
  line L316 (38.9606, 14.6256) -> (38.8819, 15.1577) construction
  line L317 (38.8819, 15.1577) -> (38.7984, 15.6894) construction
  line L318 (38.7984, 15.6894) -> (38.714, 16.2209) construction
  line L319 (38.714, 16.2209) -> (38.6083, 16.887) construction
  line L320 (38.6083, 16.887) -> (38.5032, 17.5532) construction
  line L321 (38.5032, 17.5532) -> (38.3916, 18.2186) construction
  line L322 (38.3916, 18.2186) -> (38.3556, 18.433) construction
  line L323 (38.3556, 18.433) -> (38.3166, 18.649) construction
  line L324 (38.3166, 18.649) -> (38.2491, 18.857) construction
  line L325 (38.2491, 18.857) -> (38.1664, 19.1121) construction
  line L326 (38.1664, 19.1121) -> (37.9542, 19.2598) construction
  line L327 (37.9542, 19.2598) -> (37.6499, 19.2966) construction
  line L328 (37.6499, 19.2966) -> (37.5341, 19.3106) construction
  line L329 (37.5341, 19.3106) -> (37.4162, 19.3165) construction
  line L330 (37.4162, 19.3165) -> (37.2993, 19.3166) construction
  line L331 (37.2993, 19.3166) -> (36.1164, 19.318) construction
  line L332 (36.1164, 19.318) -> (34.9335, 19.3176) construction
  line L333 (34.9335, 19.3176) -> (33.7506, 19.3174) construction
  line L334 (33.7506, 19.3174) -> (31.5219, 19.3172) construction
  line L335 (31.5219, 19.3172) -> (29.2933, 19.3182) construction
  line L336 (29.2933, 19.3182) -> (27.0646, 19.3155) construction
  line L337 (27.0646, 19.3155) -> (26.545, 19.3149) construction
  line L338 (26.545, 19.3149) -> (26.2727, 19.1294) construction
  line L339 (26.2727, 19.1294) -> (26.1828, 18.6861) construction
  line L340 (26.1828, 18.6861) -> (26.0791, 18.1748) construction
  line L341 (26.0791, 18.1748) -> (26.0064, 17.6586) construction
  line L342 (26.0064, 17.6586) -> (25.9225, 17.1442) construction
  line L343 (25.9225, 17.1442) -> (25.8227, 16.5323) construction
  line L344 (25.8227, 16.5323) -> (25.723, 15.9203) construction
  line L345 (25.723, 15.9203) -> (25.628, 15.3077) construction
  line L346 (25.628, 15.3077) -> (25.5863, 15.0388) construction
  line L347 (25.5863, 15.0388) -> (25.5377, 14.769) construction
  line L348 (25.5377, 14.769) -> (25.5261, 14.4986) construction
  line L349 (25.5261, 14.4986) -> (25.5135, 14.2034) construction
  line L350 (25.5135, 14.2034) -> (25.7129, 14.0216) construction
  line L351 (25.7129, 14.0216) -> (26.0482, 13.98) construction
  line L352 (26.0482, 13.98) -> (26.1174, 13.9715) construction
  line L353 (26.1174, 13.9715) -> (26.1889, 13.9745) construction
  line L354 (26.1889, 13.9745) -> (26.2593, 13.9745) construction
  line L355 (26.2593, 13.9745) -> (28.2529, 13.9742) construction
  line L356 (28.2529, 13.9742) -> (30.2466, 13.9743) construction
  line L357 (30.2466, 13.9743) -> (32.2403, 13.9743) construction
  spline S45 degree 3 poles (32.2357, 20.197) (33.3514, 20.197) (34.4672, 20.1961) (35.5829, 20.1976) (35.9054, 20.198) (36.1119, 20.3883) (36.0893, 20.6557) (36.0686, 20.9012) (35.8675, 21.0491) (35.5516, 21.0491) (33.3475, 21.0493) (31.1433, 21.0492) (28.9392, 21.0492) (28.9118, 21.0492) (28.8843, 21.05) (28.857, 21.0484) (28.5513, 21.0311) (28.3529, 20.8105) (28.4063, 20.5476) (28.4529, 20.3179) (28.6228, 20.1977) (28.9119, 20.1974) (30.0198, 20.1964) (31.1277, 20.197) (32.2357, 20.197) knots 0 0 0 0 1 1 1 2 2 2 3 3 3 4 4 4 5 5 5 6 6 6 7 7 7 8 8 8 8
  line L358 (32.2357, 20.197) -> (33.3514, 20.197) construction
  line L359 (33.3514, 20.197) -> (34.4672, 20.1961) construction
  line L360 (34.4672, 20.1961) -> (35.5829, 20.1976) construction
  line L361 (35.5829, 20.1976) -> (35.9054, 20.198) construction
  line L362 (35.9054, 20.198) -> (36.1119, 20.3883) construction
  line L363 (36.1119, 20.3883) -> (36.0893, 20.6557) construction
  line L364 (36.0893, 20.6557) -> (36.0686, 20.9012) construction
  line L365 (36.0686, 20.9012) -> (35.8675, 21.0491) construction
  line L366 (35.8675, 21.0491) -> (35.5516, 21.0491) construction
  line L367 (35.5516, 21.0491) -> (33.3475, 21.0493) construction
  line L368 (33.3475, 21.0493) -> (31.1433, 21.0492) construction
  line L369 (31.1433, 21.0492) -> (28.9392, 21.0492) construction
  line L370 (28.9392, 21.0492) -> (28.9118, 21.0492) construction
  line L371 (28.9118, 21.0492) -> (28.8843, 21.05) construction
  line L372 (28.8843, 21.05) -> (28.857, 21.0484) construction
  line L373 (28.857, 21.0484) -> (28.5513, 21.0311) construction
  line L374 (28.5513, 21.0311) -> (28.3529, 20.8105) construction
  line L375 (28.3529, 20.8105) -> (28.4063, 20.5476) construction
  line L376 (28.4063, 20.5476) -> (28.4529, 20.3179) construction
  line L377 (28.4529, 20.3179) -> (28.6228, 20.1977) construction
  line L378 (28.6228, 20.1977) -> (28.9119, 20.1974) construction
  line L379 (28.9119, 20.1974) -> (30.0198, 20.1964) construction
  line L380 (30.0198, 20.1964) -> (31.1277, 20.197) construction
  line L381 (31.1277, 20.197) -> (32.2357, 20.197) construction
  spline S46 degree 3 poles (37.8589, 9.5214) (38.4792, 9.5227) (38.9795, 9.9558) (38.9808, 10.4928) (38.9821, 11.0308) (38.47, 11.4757) (37.8527, 11.4728) (37.23, 11.4698) (36.7306, 11.0304) (36.7326, 10.4873) (36.7345, 9.9513) (37.2372, 9.5202) (37.8589, 9.5214) knots 0 0 0 0 1 1 1 2 2 2 3 3 3 4 4 4 4
  line L382 (37.8589, 9.5214) -> (38.4792, 9.5227) construction
  line L383 (38.4792, 9.5227) -> (38.9795, 9.9558) construction
  line L384 (38.9795, 9.9558) -> (38.9808, 10.4928) construction
  line L385 (38.9808, 10.4928) -> (38.9821, 11.0308) construction
  line L386 (38.9821, 11.0308) -> (38.47, 11.4757) construction
  line L387 (38.47, 11.4757) -> (37.8527, 11.4728) construction
  line L388 (37.8527, 11.4728) -> (37.23, 11.4698) construction
  line L389 (37.23, 11.4698) -> (36.7306, 11.0304) construction
  line L390 (36.7306, 11.0304) -> (36.7326, 10.4873) construction
  line L391 (36.7326, 10.4873) -> (36.7345, 9.9513) construction
  line L392 (36.7345, 9.9513) -> (37.2372, 9.5202) construction
  line L393 (37.2372, 9.5202) -> (37.8589, 9.5214) construction
  spline S47 degree 3 poles (27.7522, 10.4946) (27.7523, 11.0331) (27.2573, 11.4673) (26.6373, 11.4728) (26.0223, 11.4781) (25.5059, 11.0324) (25.5049, 10.4954) (25.504, 9.961) (26.0067, 9.5239) (26.6249, 9.5215) (27.2539, 9.5191) (27.752, 9.9491) (27.7522, 10.4946) knots 0 0 0 0 1 1 1 2 2 2 3 3 3 4 4 4 4
  line L394 (27.7522, 10.4946) -> (27.7523, 11.0331) construction
  line L395 (27.7523, 11.0331) -> (27.2573, 11.4673) construction
  line L396 (27.2573, 11.4673) -> (26.6373, 11.4728) construction
  line L397 (26.6373, 11.4728) -> (26.0223, 11.4781) construction
  line L398 (26.0223, 11.4781) -> (25.5059, 11.0324) construction
  line L399 (25.5059, 11.0324) -> (25.5049, 10.4954) construction
  line L400 (25.5049, 10.4954) -> (25.504, 9.961) construction
  line L401 (25.504, 9.961) -> (26.0067, 9.5239) construction
  line L402 (26.0067, 9.5239) -> (26.6249, 9.5215) construction
  line L403 (26.6249, 9.5215) -> (27.2539, 9.5191) construction
  line L404 (27.2539, 9.5191) -> (27.752, 9.9491) construction
  line L405 (27.752, 9.9491) -> (27.7522, 10.4946) construction
  spline S48 degree 3 poles (7.9309, 35.7631) (6.9516, 35.763) (3.1923, 28.7681) (4.1998, 28.3225) (4.6339, 28.1306) (10.2939, 27.728) (11.664, 28.3225) (12.6319, 28.7425) (8.957, 35.7632) (7.9309, 35.7631) knots 0 0 0 0 1 1 1 2 2 2 3 3 3 3
  line L406 (7.9309, 35.7631) -> (6.9516, 35.763) construction
  line L407 (6.9516, 35.763) -> (3.1923, 28.7681) construction
  line L408 (3.1923, 28.7681) -> (4.1998, 28.3225) construction
  line L409 (4.1998, 28.3225) -> (4.6339, 28.1306) construction
  line L410 (4.6339, 28.1306) -> (10.2939, 27.728) construction
  line L411 (10.2939, 27.728) -> (11.664, 28.3225) construction
  line L412 (11.664, 28.3225) -> (12.6319, 28.7425) construction
  line L413 (12.6319, 28.7425) -> (8.957, 35.7632) construction
  line L414 (8.957, 35.7632) -> (7.9309, 35.7631) construction
  line L415 (7.4884, 30.4763) -> (7.3637, 34.0871)
  line L416 (7.3637, 34.0871) -> (8.4981, 34.0871)
  line L417 (8.4981, 34.0871) -> (8.3734, 30.4763)
  line L418 (8.3734, 30.4763) -> (7.4884, 30.4763)
  line L419 (7.9309, 49.0709) -> (7.9309, 33.8054)
  line L420 (7.9309, 35.8143) -> (7.9309, 26.8372)
  circle A0 centre (7.9309, 29.3763) radius 0.65
  point P0 (0, 0)
  dimension "d0" = 1.1345
  dimension "d1" = 0.885
  dimension "d2" = 3.6108
  dimension "d3" = 1.3
  dimension "d4" = 1.1
  constraints: 14 end point, 2 point on line, 2 vertical, 1 centre point, 1 collinear, 137 other
  measures "d0" distance of L415.end L416.end
  measures "d1" distance of L417.end L415.start
  measures "d2" distance between parallel lines of L418 L416
  measures "d3" diameter of A0
  measures "d4" distance from line of A0.centre L418